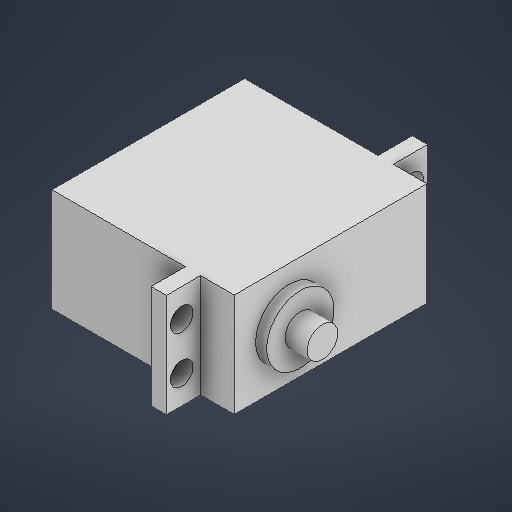
# Autodesk Inventor part: servomot
Saved by Autodesk Inventor 2026 (Build 300175000, 175)
## iProperties
Created: 2025-06-07
Part Number: servomot
Material: Générique
Document SubType Name: Modeling
Designer: Diogo
Density: 1 g/cm^3
Appearance: Par défaut
Author: Diogo
Autodesk Inventor part; units mm, degrees
ref_plane "YZ Plane" through (0, 0, 0) normal (1, 0, 0) x (0, 1, 0)
ref_plane "XZ Plane" through (0, 0, 0) normal (0, 1, 0) x (-1, 0, 0)
ref_plane "XY Plane" through (0, 0, 0) normal (0, 0, 1) x (1, 0, 0)
sketch "Esquisse1" plane through (0, 0, 0) normal (0, 1, 0) x (-1, 0, 0)
  line L0 (0, 6.8342) -> (0, -24.6658)
  line L1 (29.8, -24.6658) -> (29.8, 6.8342)
  line L2 (8, -24.6658) -> (8, -30.2658)
  line L3 (8, -30.2658) -> (5.5, -30.2658)
  line L4 (5.5, -30.2658) -> (5.5, -24.6658)
  line L5 (0, -24.6658) -> (5.5, -24.6658)
  line L6 (8, -24.6658) -> (29.8, -24.6658)
  line L7 (8, 6.8342) -> (8, 12.4342)
  line L8 (8, 12.4342) -> (5.5, 12.4342)
  line L9 (5.5, 12.4342) -> (5.5, 6.8342)
  line L10 (29.8, 6.8342) -> (8, 6.8342)
  line L11 (5.5, 6.8342) -> (0, 6.8342)
  point P0 (0, 0)
  dimension "d0" = 31.5
  dimension "d1" = 29.8
  dimension "d3" = 2.5
  dimension "d6" = 2.5
  dimension "d25" = 5.6
  dimension "d26" = 5.6
  dimension "d27" = 42.7
  constraints: 24 end point, 3 horizontal, 3 parallel, 3 perpendicular, 1 collinear, 1 vertical
  measures "d0" distance of L0.start L0.end
  measures "d1" distance of L0.end L1.start
  measures "d3" distance of L2.end L3.end
  measures "d6" distance of L8.end L7.end
  measures "d25" distance of L7.start L7.end
  measures "d26" distance of L2.start L2.end
  measures "d27" distance between parallel lines of L8 L3
extrude "Extrusion1" add sketch "Esquisse1" along normal blind 16.9
sketch "Esquisse2" plane through (-8, 0, 6.8342) normal (-1, 0, 0) x (0, 0, 1)
  line L0 (0, 16.9) -> (5.6, 16.9) projected
  line L1 (5.6, 0) -> (5.6, 16.9) projected
  point P0 (-6.8342, 0)
  point P1 (3.1, 12.3)
  dimension "d10" = 4.6
  dimension "d36" = 2.5
  measures "d10" distance from line of L0 point (3.1, 12.3)
  measures "d36" distance from line of L1 point (3.1, 12.3)
hole "Perçage1" at (-8, 12.3, 9.9342) direction (1, 0, 0) diameter 3.7 end through all
pattern_linear "Réseau rectangulaire1" count 2 spacing 7.7 along (0, -1, 0) count 2 spacing 37.7 along (0, 0, -1) of "Perçage1"
sketch "Esquisse3" plane through (0, 0, 6.8342) normal (1, 0, 0) x (0, 0, -1)
  circle A0 centre (9, 8.45) radius 5.5
  line L0 (0, 0) -> (0, 16.9) construction
  line L1 (0, 8.45) -> (58.4602, 8.45) construction
  line L2 (-5.6, 0) -> (-5.6, 16.9) construction
  point P0 (6.8342, 0)
  dimension "d28" = 11
  dimension "d29" = 14.6
  constraints: 2 end point, 1 centre point, 1 horizontal, 1 midpoint, 1 point on line
  measures "d28" diameter of A0
  measures "d29" distance from line of L2 A0.centre
extrude "Extrusion2" add sketch "Esquisse3" along normal blind 1.8
sketch "Esquisse4" plane through (1.8, 8.45, -2.1658) normal (1, 0, 0) x (0, 0, -1)
  circle A0 centre (0, 0) radius 2.5
  point P0 (-2.1658, -8.45)
  dimension "d33" = 5
  constraints: 1 centre point
  measures "d33" diameter of A0
extrude "Extrusion3" add sketch "Esquisse4" along normal blind 3.6
